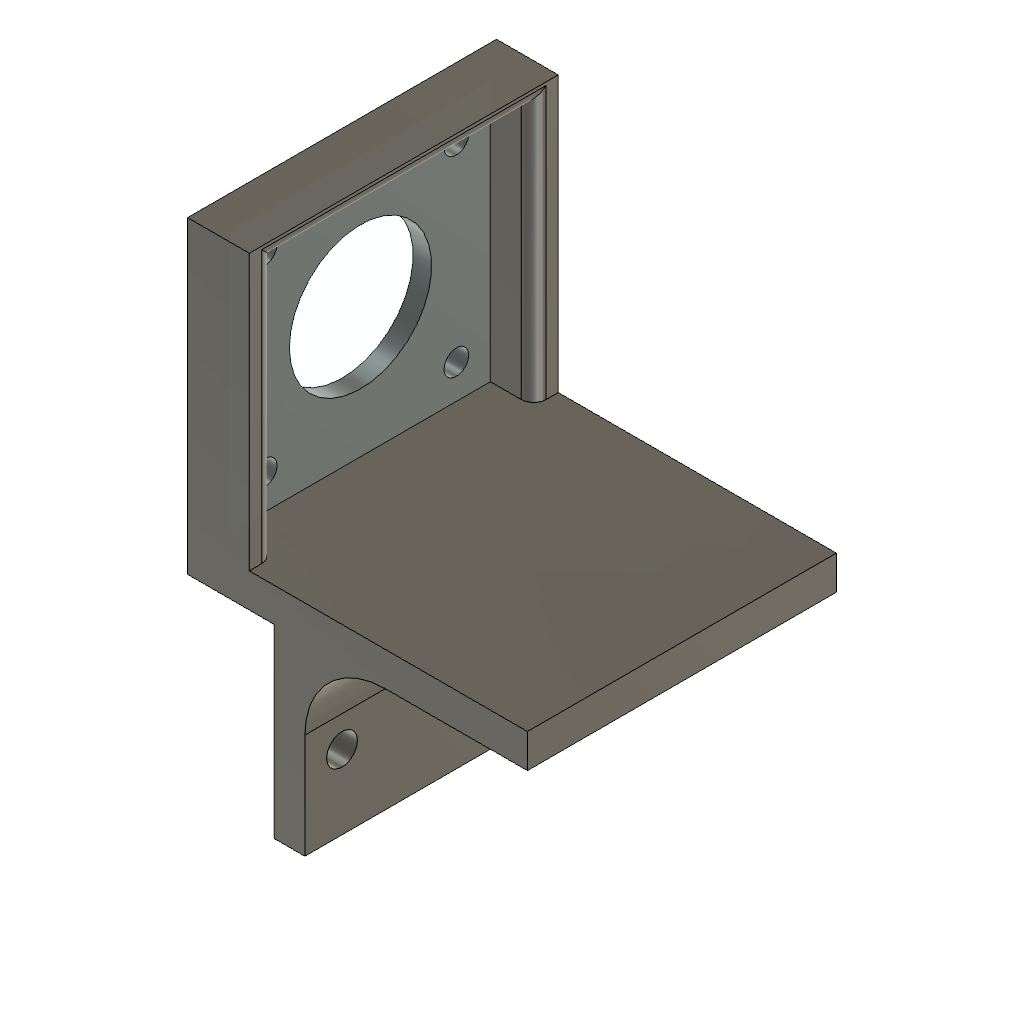
Conv Belt - Motor End Motor Side (Autodesk Fusion 360 design; units mm, degrees)
Autodesk Fusion 360 part; units mm, degrees
box "BoxPrimitive1" add length 50 width 10 height 50 placed x (0, -1, 0) y (1, 0, 0) z (0, 0, 1) at (10, 0, 0)
sketch "Sketch3" plane through (20, 0, 0) normal (1, 0, 0) x (0, 1, 0)
  line L0 (-50, 50) -> (-50, 0)
  line L1 (-50, 0) -> (0, 0)
  line L2 (0, 0) -> (0, 50)
  line L3 (0, 50) -> (-50, 50)
  line L4 (0, 0) -> (0, 3)
  line L5 (0, 3) -> (-53, 3)
  line L6 (0, 50) -> (-50, 3)
  line L7 (0, 3) -> (-50, 50)
  circle A0 centre (-25, 26.5) radius 11.5
  dimension "d16" = 3
  dimension "d17" = 23
  constraint coincident L1.end L2.start
  constraint perpendicular L1 L4
  constraint perpendicular L0 L5
  constraint coincident L2.end L3.start
  constraint coincident L5 L6.end
  constraint coincident L0 L6.end
  constraint coincident L0.start L3.end
  constraint midpoint L6 A0.centre
  measures "d16" distance of L1.end L4.end
  measures "d17" diameter of A0
extrude "Extrude2" cut sketch "Sketch3" against normal blind 10 contours L6 L7 A0 | L6 L7 A0 | L6 L7 A0 | L6 L7 A0
sketch "Sketch9" plane through (20, 0, 0) normal (1, 0, 0) x (0, 1, 0)
  circle A0 centre (-25, 26.5) radius 11.5
  line L0 (-50, 50) -> (-50, 0)
  line L1 (-50, 0) -> (0, 0)
  line L2 (0, 0) -> (0, 50)
  line L3 (0, 50) -> (-50, 50)
  line L4 (-4, 47.5) -> (-46, 47.5)
  line L5 (-46, 47.5) -> (-46, 5.5)
  line L6 (-46, 5.5) -> (-4, 5.5)
  line L7 (-4, 5.5) -> (-4, 47.5)
  line L8 (-4, 47.5) -> (-46, 5.5) construction
  line L9 (-46, 47.5) -> (-4, 5.5) construction
  line L10 (-46, 5.5) -> (-50, 5.5)
  line L11 (-4, 5.5) -> (0, 5.5)
  point P0 (-25, 26.5)
  dimension "d20" = 42
  dimension "d21" = 42
  constraint horizontal L4
  constraint perpendicular L4 L5
  constraint parallel L4 L6
  constraint parallel L5 L7
  constraint coincident L8 P0
  constraint coincident L9 P0
  constraint coincident P0 A0.centre
  constraint coincident L0 L10.end
  constraint perpendicular L0 L10
  constraint coincident L2 L11.end
  constraint perpendicular L2 L11
  measures "d20" distance of L5.end L6.end
  measures "d21" distance of L4.end L5.end
extrude "Extrude3" cut sketch "Sketch9" against normal blind 7 contours L4 L5 L6 L7
sketch "Sketch11" plane through (13, 0, 0) normal (1, 0, 0) x (0, 1, 0)
  circle A0 centre (-25, 26.5) radius 11.5
  line L0 (-4, 5.5) -> (-4, 47.5)
  line L1 (-4, 47.5) -> (-46, 47.5)
  line L2 (-46, 47.5) -> (-46, 5.5)
  line L3 (-46, 5.5) -> (-4, 5.5)
  line L4 (-4, 47.5) -> (-9.5, 47.5)
  line L5 (-9.5, 47.5) -> (-9.5, 42)
  line L6 (-9.5, 42) -> (-4, 42)
  line L7 (-4, 42) -> (-4, 47.5)
  circle A1 centre (-9.5, 42) radius 2
  line L8 (-46, 47.5) -> (-40.5, 47.5)
  line L9 (-40.5, 47.5) -> (-40.5, 42)
  line L10 (-40.5, 42) -> (-46, 42)
  line L11 (-46, 42) -> (-46, 47.5)
  circle A2 centre (-40.5, 42) radius 2
  line L12 (-46, 5.5) -> (-40.5, 5.5)
  line L13 (-40.5, 5.5) -> (-40.5, 11)
  line L14 (-40.5, 11) -> (-46, 11)
  line L15 (-46, 11) -> (-46, 5.5)
  circle A3 centre (-40.5, 11) radius 2
  line L16 (-4, 5.5) -> (-9.5, 5.5)
  line L17 (-9.5, 5.5) -> (-9.5, 11)
  line L18 (-9.5, 11) -> (-4, 11)
  line L19 (-4, 11) -> (-4, 5.5)
  circle A4 centre (-9.5, 11) radius 2
  dimension "d42" = 5.5
  dimension "d43" = 5.5
  dimension "d44" = 4
  dimension "d45" = 5.5
  dimension "d46" = 5.5
  dimension "d47" = 4
  dimension "d48" = 5.5
  dimension "d49" = 5.5
  dimension "d50" = 4
  dimension "d51" = 5.5
  dimension "d52" = 5.5
  dimension "d53" = 4
  constraint horizontal L4
  constraint vertical L5
  constraint horizontal L6
  constraint vertical L7
  constraint coincident L0.end L1.start
  constraint coincident L5.end L6.start
  constraint horizontal L8
  constraint vertical L9
  constraint horizontal L10
  constraint vertical L11
  constraint coincident L1.end L2.start
  constraint coincident L9.end L10.start
  constraint horizontal L12
  constraint vertical L13
  constraint horizontal L14
  constraint vertical L15
  constraint coincident L2.end L3.start
  constraint coincident L13.end L14.start
  constraint horizontal L16
  constraint vertical L17
  constraint horizontal L18
  constraint vertical L19
  constraint coincident L0.start L3.end
  constraint coincident L17.end L18.start
  measures "d42" distance of L0.end L4.end
  measures "d43" distance of L0.end L6.end
  measures "d44" diameter of A1
  measures "d45" distance of L1.end L8.end
  measures "d46" distance of L1.end L10.end
  measures "d47" diameter of A2
  measures "d48" distance of L2.end L12.end
  measures "d49" distance of L2.end L14.end
  measures "d50" diameter of A3
  measures "d51" distance of L0.start L16.end
  measures "d52" distance of L0.start L18.end
  measures "d53" diameter of A4
extrude "Extrude5" add sketch "Sketch9" along normal blind 45 contours L0 L1 L2 L6 L10 L11
fillet "Fillet1" radius 2 3 edges at (20, -25, 47.5) (20, -46, 26.5) (20, -4, 26.5)
extrude "Extrude6" cut sketch "Sketch11" against normal blind 3 contours L17 L18 A4 | L17 L18 A4 | L5 L6 A1 | L5 L6 A1 | L13 L14 A3 | L13 L14 A3 | L9 L10 A2 | L9 L10 A2
sketch "Sketch12" plane through (0, 0, 0) normal (0, 0, -1) x (1, 0, 0)
  line L0 (65, 50) -> (10, 50)
  line L1 (10, 50) -> (10, 0)
  line L2 (10, 0) -> (65, 0)
  line L3 (65, 0) -> (65, 50)
  line L4 (10, 50) -> (24, 50)
  line L5 (24, 50) -> (24, 0)
  line L6 (24, 0) -> (10, 0)
  line L7 (10, 0) -> (10, 50)
  line L8 (24, 50) -> (29, 50)
  line L9 (29, 50) -> (29, 0)
  line L10 (29, 0) -> (24, 0)
  line L11 (24, 0) -> (24, 50)
  dimension "d56" = 14
  dimension "d57" = 50
  dimension "d58" = 5
  dimension "d59" = 50
  constraint horizontal L4
  constraint vertical L5
  constraint horizontal L6
  constraint vertical L7
  constraint coincident L0.end L1.start
  constraint horizontal L8
  constraint vertical L9
  constraint horizontal L10
  constraint vertical L11
  measures "d56" distance of L0.end L4.end
  measures "d57" distance of L0.end L1.end
  measures "d58" distance of L4.end L8.end
  measures "d59" distance of L4.end L5.end
extrude "Extrude7" add sketch "Sketch12" along normal blind 30 contours L0 L2 L5 L8 L9 L10 L11
fillet "Fillet2" radius 13 1 edges at (29, -25, 0)
sketch "Sketch14" plane through (24, 0, 0) normal (-1, 0, 0) x (0, -1, 0)
  line L0 (50, 0) -> (0, 0)
  line L1 (0, 0) -> (0, -30)
  line L2 (0, -30) -> (50, -30)
  line L3 (50, -30) -> (50, 0)
  circle A0 centre (6, -18) radius 2.5
  circle A1 centre (44, -18) radius 2.5
  dimension "d92" = 5
  dimension "d93" = 5
  dimension "d94" = 38
  dimension "d95" = 18
  dimension "d96" = 18
  dimension "d97" = 6
  measures "d92" diameter of A0
  measures "d93" diameter of A1
  measures "d94" horizontal distance of A0.centre A1.centre
  measures "d95" distance of L0 A0.centre
  measures "d96" distance of L0 A1.centre
  measures "d97" distance of L3 A1.centre
extrude "Extrude9" cut sketch "Sketch14" against normal blind 5 contours A0 | A1
sketch "Sketch17" plane through (13, 0, 0) normal (1, 0, 0) x (0, 1, 0)
  circle A0 centre (-40.5, 11) radius 2
  circle A1 centre (-9.5, 42) radius 2
  circle A2 centre (-40.5, 42) radius 2
  circle A3 centre (-9.5, 11) radius 2
  circle A4 centre (-25, 26.5) radius 11.5
  line L0 (-4, 5.5) -> (-4, 47.5)
  line L1 (-4, 47.5) -> (-46, 47.5)
  line L2 (-46, 47.5) -> (-46, 5.5)
  line L3 (-46, 5.5) -> (-4, 5.5)
